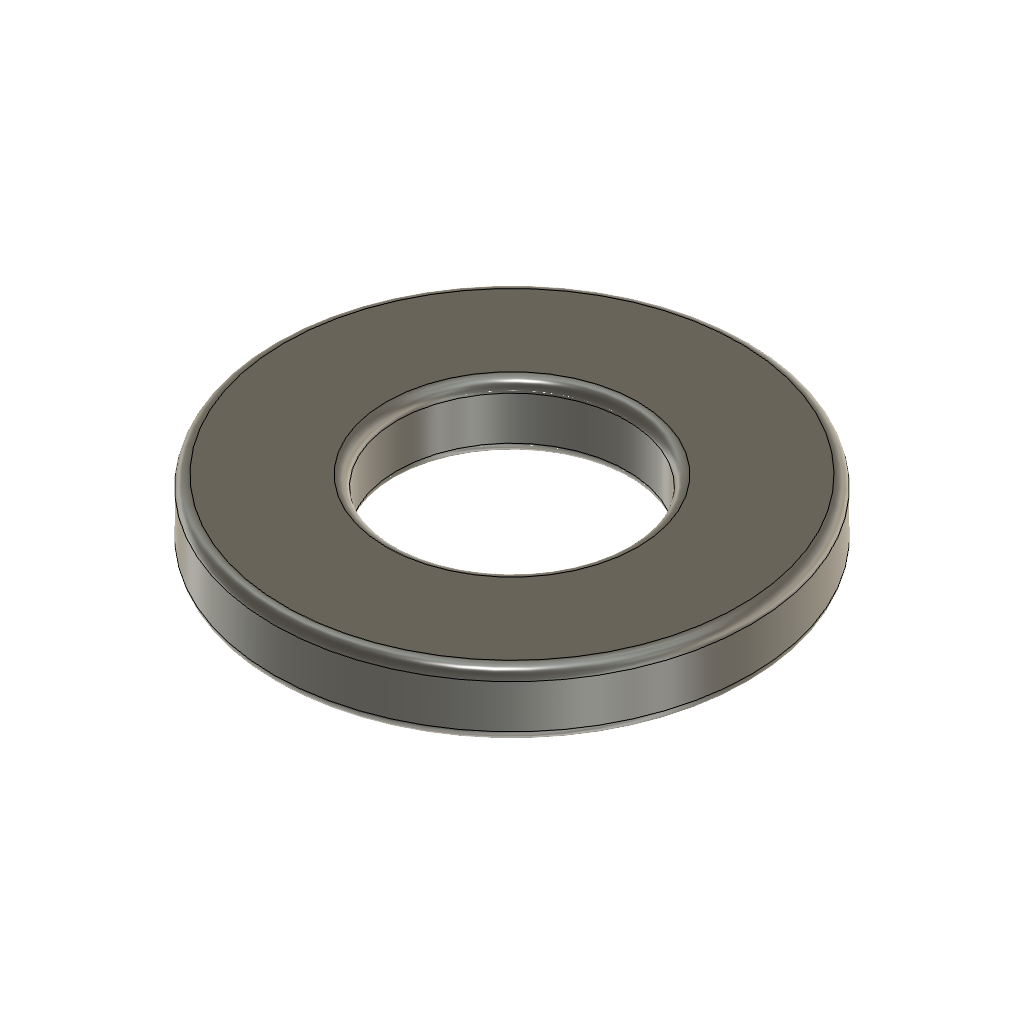
spacer_1p5mm (Autodesk Fusion 360 design; units mm, degrees)
part number: 2026-10-04-17-38-31-529
Autodesk Fusion 360 part; units mm, degrees
sketch "Sketch1" plane through (0, 0, 0) normal (0, 0, 1) x (1, 0, 0)
  circle A0 centre (0, 0) radius 2.65
  circle A1 centre (0, 0) radius 5.5
  dimension "d1" = 5.3
  dimension "d2" = 11
  constraint coincident A0.centre A1.centre
  measures "d1" diameter of A0
  measures "d2" diameter of A1
extrude "Extrude1" add sketch "Sketch1" along normal blind 1.5
fillet "Fillet1" radius 0.25 4 edges at (-2.4707, 0.9583, 1.5) (-5.1278, -1.9889, 1.5) (-5.1278, -1.9889, 0) (-2.4707, 0.9583, 0)
